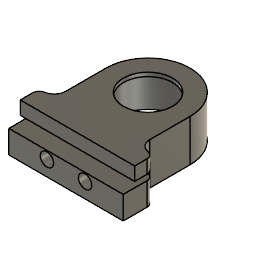
Sensor_Housing_Parametric (Autodesk Fusion 360 design; units mm, degrees)
Autodesk Fusion 360 part; units mm, degrees
sketch "Sketch1" plane through (0, 0, 0) normal (0, 0, 1) x (1, 0, 0)
  circle A0 centre (0, 0) radius 12.85
  line L0 (0, 0) -> (0, -20.85) construction
  line L1 (-22, 0) -> (-22, -27)
  line L2 (22, 0) -> (22, -27)
  line L3 (-22, -27) -> (22, -27)
  arc A1 (22, 0) -> (-22, 0) centre (0, 0) ccw
  line L4 (-20, -25) -> (20, -25)
  line L5 (20, 0) -> (20, -25)
  arc A2 (20, 0) -> (-20, 0) centre (0, 0) ccw
  line L6 (-20, 0) -> (-20, -25)
  dimension "d1" = 25.7
  dimension "d5" = 2
  dimension "d8" = 25
  dimension "d9" = 22
  dimension "d10" = 20.85
  constraint coincident A0.centre L0.start
  constraint vertical L0
  constraint tangent L1 A1
  constraint parallel L0 L1
  constraint symmetric L0 L1.start L2.start
  constraint symmetric L0 L1.end L2.end
  constraint concentric A0 A1
  measures "d1" diameter of A0
  measures "d8" distance of L4.end L5.start
  measures "d9" radius of A1
  measures "d10" vertical distance of A0.centre L0.end
extrude "Extrude1" add sketch "Sketch1" along normal blind 2 contours L1 L2 L3 A1 | L4 L5 A2 L6
extrude "Extrude2" add sketch "Sketch1" against normal blind 20 contours L1 L2 L3 A1
sketch "Sketch2" plane through (0, 0, 0) normal (1, 0, 0) x (0, 1, 0)
  line L0 (-27, -20) -> (-27, 2)
  line L1 (-27, 2) -> (-37, 2)
  line L2 (-37, 2) -> (-37, -5)
  line L3 (-37, -5) -> (-27, -5)
  line L4 (-27, -20) -> (-43, -20)
  line L5 (-43, -20) -> (-43, -7.9)
  line L6 (-43, -7.9) -> (-27, -7.9)
  dimension "d11" = 10
  dimension "d12" = 7
  dimension "d13" = 16
  dimension "d15" = 12.1
  constraint coincident L0.end L1.start
  constraint perpendicular L0 L1
  constraint perpendicular L1 L2
  constraint coincident L0 L3.end
  constraint perpendicular L0 L3
  constraint coincident L0.start L4.start
  constraint perpendicular L0 L4
  constraint perpendicular L4 L5
  constraint coincident L0 L6.end
  constraint perpendicular L0 L6
  measures "d11" distance of L0.end L1.end
  measures "d12" distance of L1 L3
  measures "d13" distance of L0.start L4.end
  measures "d15" distance of L4 L6
extrude "Extrude3" add sketch "Sketch2" along normal mid plane 60
sketch "Sketch3" plane through (0, -25, 0) normal (0, 1, 0) x (-1, 0, 0)
  line L0 (20, 0) -> (-20, 0)
  line L1 (-20, 0) -> (-20, -20)
  line L2 (-20, -20) -> (20, -20)
  line L3 (20, -20) -> (20, 0)
  line L4 (0, -20) -> (0, -1) construction
  line L5 (21, -12) -> (-21, -12) construction
  circle A0 centre (10, -12) radius 3.5
  circle A1 centre (-10, -12) radius 3.5
  dimension "d18" = 7
  dimension "d19" = 10
  dimension "d20" = 21
  dimension "d21" = 21
  dimension "d22" = 8
  dimension "d23" = 11
  constraint midpoint L2 L4.start
  constraint perpendicular L0 L4
  constraint perpendicular L1 L5
  constraint coincident L5 A0.centre
  constraint symmetric L4 A0 A1
  measures "d18" diameter of A0
  measures "d19" distance of L4 A0.centre
  measures "d20" distance of L4 L5.end
  measures "d21" distance of L4 L5.start
  measures "d22" distance of L4.start L5
  measures "d23" distance of L4.end L5
extrude "Extrude4" cut sketch "Sketch3" against normal blind 24 contours A0 | A1
fillet "Fillet1" radius 3.5 4 edges at (30, -27, -13.95) (30, -27, -1.5) (-30, -27, -1.5) (-30, -27, -13.95)
fillet "Fillet2" radius 6 4 edges at (-22, -27, -13.95) (-22, -27, -1.5) (22, -27, -1.5) (22, -27, -13.95)
